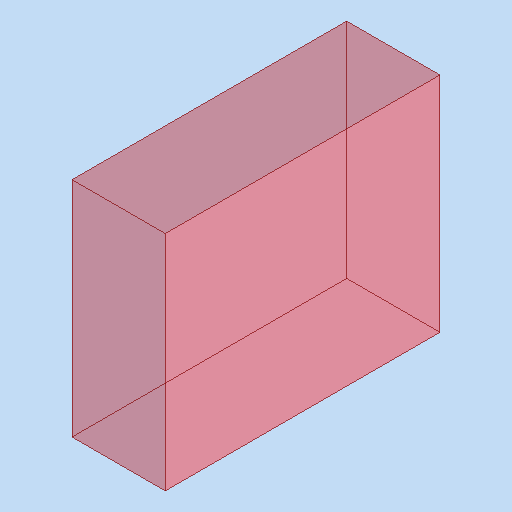
# Autodesk Inventor part: MM0937AN106_G25_700
Saved by Autodesk Inventor 2023.3 (Build 273359000, 359)
## iProperties
Created: 2023-11-10
Part Number: MM0937AN106_G25_700
Material: Generisch
Description: =<RBPARTNOTITLE2>
Document SubType Name: Modeling
Designer: FSM9BW
Mass: 360.994 g
Surface Area: 80.14 cm^2
Volume: 41.022 cm^3
Density: 8.8 g/cm^3
Appearance: rot - klar AnP
RBPARTMADEOF: --
RBDRAWINGMISSINGSPEC: --
AnP_Kategorie: 2
RBPARTNOTITLE2: Sub-D-Stecker
RBSURFACE: --
RBPARTNOTITLE1: Sub-D-connector
AnP_Material: =<Material>
RBMATERIAL: --
RBMATNO: =<Part Number>
RBPARTNO: SIEHE MNR
Author: FSM9BW
Keywords: =<RBPARTMADEOF>
Comments: =<RBSURFACE2>
Revision Number: 01
Autodesk Inventor part; units mm, degrees
ref_plane "YZ Plane" through (0, 0, 0) normal (1, 0, 0) x (0, 1, 0)
ref_plane "XZ Plane" through (0, 0, 0) normal (0, 1, 0) x (-1, 0, 0)
ref_plane "XY Plane" through (0, 0, 0) normal (0, 0, 1) x (1, 0, 0)
sketch "Skizze1" plane through (0, 0, 0) normal (0, 0, 1) x (1, 0, 0)
  line L0 (-9, -26.5) -> (9, -26.5)
  line L1 (9, -26.5) -> (9, 26.5)
  line L2 (9, 26.5) -> (-9, 26.5)
  line L3 (-9, 26.5) -> (-9, -26.5)
  line L4 (-12.6, 0) -> (12.6, 0) projected
  line L5 (0, -37.1) -> (0, 37.1) projected
  point P0 (0, 0)
  dimension "d0" = 18
  dimension "d1" = 53
  constraints: 8 end point, 2 parallel, 1 horizontal, 1 perpendicular, 2 other
  measures "d0" distance of L1.end L2.end
  measures "d1" distance of L2.end L0.start
extrude "Extrusion1" add sketch "Skizze1" along normal blind 43
